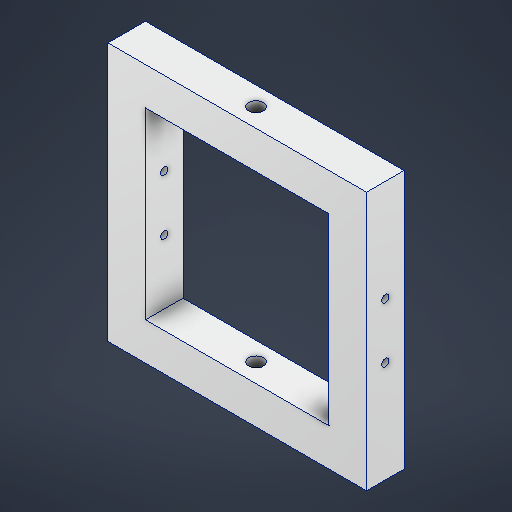
# Autodesk Inventor part: inner frame
Saved by Autodesk Inventor 2026.1 (Build 301233000, 233)
## iProperties
Created: 2025-11-10
Part Number: inner frame
Material: Aluminum 6061
Document SubType Name: Modeling
Designer: shiva
Mass: 8338.98 g
Surface Area: 2431.9 cm^2
Volume: 3088.51 cm^3
Density: 2.7 g/cm^3
Appearance: Aluminum - Flat
Author: shiva
Autodesk Inventor part; units mm, degrees
ref_plane "YZ Plane" through (0, 0, 0) normal (1, 0, 0) x (0, 1, 0)
ref_plane "XZ Plane" through (0, 0, 0) normal (0, 1, 0) x (-1, 0, 0)
ref_plane "XY Plane" through (0, 0, 0) normal (0, 0, 1) x (1, 0, 0)
sketch "Sketch3" plane through (0, 0, 0) normal (0, 0, 1) x (1, 0, 0)
  line L0 (-175, 175) -> (175, 175)
  line L1 (175, 175) -> (175, -175)
  line L2 (175, -175) -> (-175, -175)
  line L3 (-175, -175) -> (-175, 175)
  line L4 (-175, 175) -> (175, -175) construction
  line L5 (175, 175) -> (-175, -175) construction
  line L6 (-124.2, 124.2) -> (124.2, 124.2)
  line L7 (124.2, 124.2) -> (124.2, -124.2)
  line L8 (124.2, -124.2) -> (-124.2, -124.2)
  line L9 (-124.2, -124.2) -> (-124.2, 124.2)
  line L10 (-124.2, 124.2) -> (124.2, -124.2) construction
  line L11 (124.2, 124.2) -> (-124.2, -124.2) construction
  point P0 (0, 0)
  dimension "d7" = 350
  dimension "d9" = 248.4
  constraints: 24 end point, 4 midpoint, 4 parallel, 4 perpendicular, 2 horizontal
  measures "d7" distance of L0.end L1.end
  measures "d9" distance of L6.end L7.end
extrude "Extrusion1" add sketch "Sketch3" along normal blind 50.8
sketch "Sketch5" plane through (-175, -175, 0) normal (0, -1, 0) x (1, 0, 0)
  line L0 (350, 50.8) -> (0, 50.8) projected
  line L1 (350, 0) -> (350, 50.8) projected
  line L2 (0, 50.8) -> (350, 50.8)
  line L3 (350, 50.8) -> (350, 0)
  line L4 (350, 0) -> (0, 0)
  line L5 (0, 0) -> (0, 50.8)
  circle A0 centre (175, 25.4) radius 10 projected
  circle A1 centre (175, 25.4) radius 10
  point P0 (175, 0)
  constraints: 8 end point, 2 parallel, 1 centre point, 1 coincident, 1 horizontal, 1 perpendicular
sketch "Sketch7" plane through (175, -175, 0) normal (1, 0, 0) x (0, 0, -1)
  line L0 (-25.4, 212.5) -> (-25.4, 137.5)
  circle A0 centre (-25.4, 212.5) radius 5
  circle A1 centre (-25.4, 137.5) radius 5
  line L1 (0, 0) -> (-50.8, 0) projected
  line L2 (0, 350) -> (-50.8, 350) projected
  line L3 (-50.8, 350) -> (0, 350)
  line L4 (-25.4, 350) -> (-25.4, 212.5)
  point P0 (0, 175)
  point P1 (-25.4, 0)
  dimension "d21" = 75
  dimension "d22" = 10
  dimension "d23" = 10
  dimension "d30" = 350
  dimension "d31" = 137.5
  dimension "d32" = 137.5
  constraints: 6 end point, 2 centre point, 2 coincident, 2 midpoint, 1 horizontal, 1 vertical
  measures "d21" distance of L0.start L0.end
  measures "d22" diameter of A0
  measures "d23" diameter of A1
  measures "d30" distance between parallel lines of L1 L2
  measures "d31" distance of L4.start L4.end
  measures "d32" distance of point (-25.4, 0) L0.end
extrude "Extrusion5" cut sketch "Sketch7" against normal through all
extrude "Extrusion6" cut sketch "Sketch5" against normal through all contours A0
body "Solid2"
